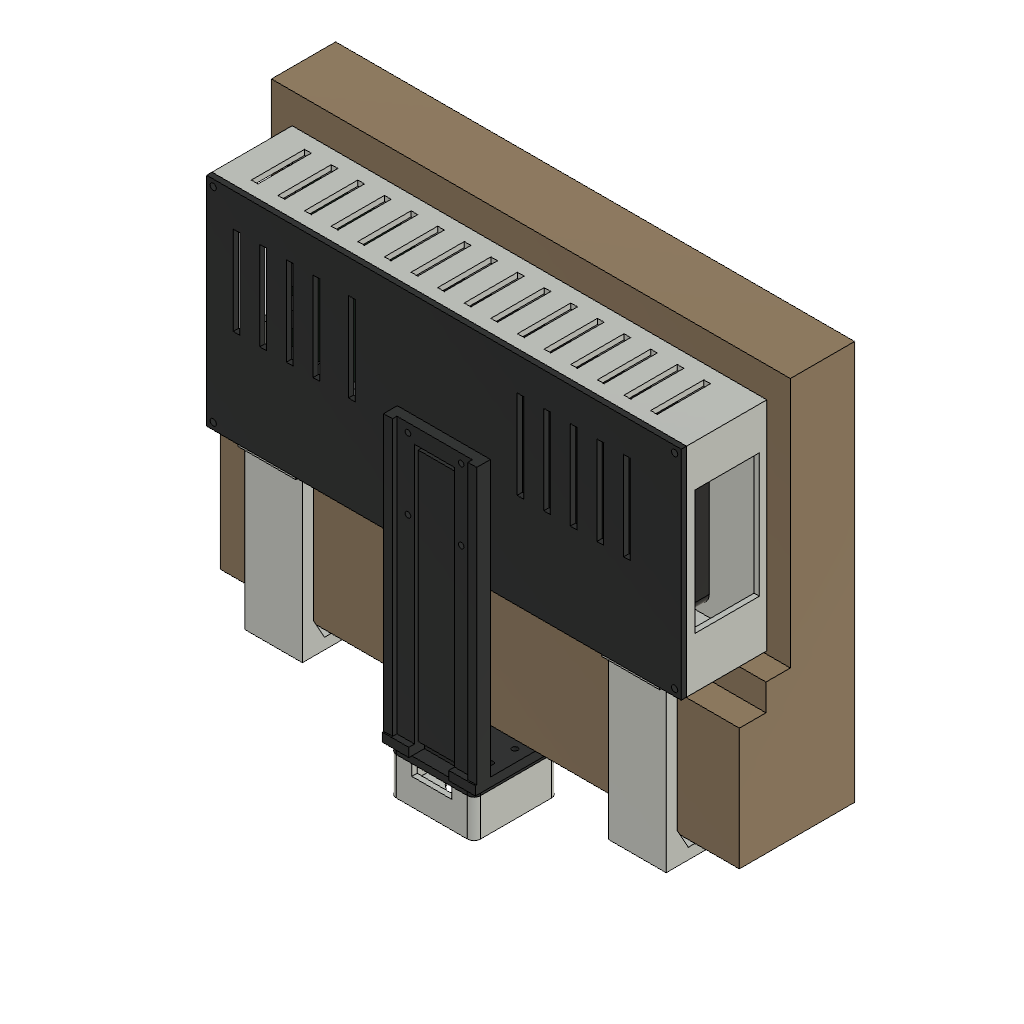
doorframe-camera-v5 (Autodesk Fusion 360 design; units mm, degrees)
part number: 2026-11-08-18-06-19-159
part number: 2026-11-08-18-06-29-546
part number: 2026-11-08-18-06-30-123
part number: 2026-11-08-18-06-36-129
part number: 2026-11-08-18-06-39-085
part number: 2026-11-08-18-06-42-850
part number: 2026-11-08-20-43-08-468
part number: 2026-11-08-20-43-10-155
part number: 2026-11-08-20-43-11-426
part number: 2026-11-08-20-43-11-993
part number: 2026-11-08-20-43-12-596
part number: 2026-11-08-20-43-14-141
part number: 2026-11-08-20-43-15-002
part number: 2026-11-08-20-43-15-243
Autodesk Fusion 360 part; units mm, degrees
(part 1 of 2)
ref_plane "WorkPlane1" through (0, 0, 4.4) normal (0, 0, 1) x (1, 0, 0) in component "REFERENCE - INIU P51L-E2 115 x 73 x 29 mm"
sketch "INIU envelope - check supplied cable position outline" plane through (0, 0, 4.4) normal (0, 0, 1) x (1, 0, 0) in component "REFERENCE - INIU P51L-E2 115 x 73 x 29 mm"
  line L0 (11, 7.5) -> (116, 7.5)
  line L1 (121, 12.5) -> (121, 75.5)
  line L2 (116, 80.5) -> (11, 80.5)
  line L3 (6, 75.5) -> (6, 12.5)
  arc A0 (116, 7.5) -> (121, 12.5) centre (116, 12.5) ccw
  arc A1 (121, 75.5) -> (116, 80.5) centre (116, 75.5) ccw
  arc A2 (11, 80.5) -> (6, 75.5) centre (11, 75.5) ccw
  arc A3 (6, 12.5) -> (11, 7.5) centre (11, 12.5) ccw
extrude "INIU envelope - check supplied cable position" add sketch "INIU envelope - check supplied cable position outline" along normal blind 29 makes body 1 in component "REFERENCE - INIU P51L-E2 115 x 73 x 29 mm"
ref_plane "WorkPlane1" through (0, 0, 44.4) normal (0, 0, 1) x (1, 0, 0) in component "REFERENCE - Raspberry Pi4 rotated ports"
sketch "Pi PCB 85 x 56 x 1.6 outline" plane through (0, 0, 44.4) normal (0, 0, 1) x (1, 0, 0) in component "REFERENCE - Raspberry Pi4 rotated ports"
  line L0 (9, 15) -> (88, 15)
  line L1 (91, 18) -> (91, 68)
  line L2 (88, 71) -> (9, 71)
  line L3 (6, 68) -> (6, 18)
  arc A0 (88, 15) -> (91, 18) centre (88, 18) ccw
  arc A1 (91, 68) -> (88, 71) centre (88, 68) ccw
  arc A2 (9, 71) -> (6, 68) centre (9, 68) ccw
  arc A3 (6, 18) -> (9, 15) centre (9, 18) ccw
extrude "Pi PCB 85 x 56 x 1.6" add sketch "Pi PCB 85 x 56 x 1.6 outline" along normal blind 1.6 separate body makes body 2 in component "REFERENCE - Raspberry Pi4 rotated ports"
ref_plane "WorkPlane2" through (0, 0, 44.3) normal (0, 0, 1) x (1, 0, 0) in component "REFERENCE - Raspberry Pi4 rotated ports"
sketch "Pi mounting holes layout" plane through (0, 0, 44.3) normal (0, 0, 1) x (1, 0, 0) in component "REFERENCE - Raspberry Pi4 rotated ports"
  circle A0 centre (87.5, 67.5) radius 1.375
  circle A1 centre (29.5, 67.5) radius 1.375
  circle A2 centre (87.5, 18.5) radius 1.375
  circle A3 centre (29.5, 18.5) radius 1.375
extrude "Pi mounting holes" cut sketch "Pi mounting holes layout" along normal blind 2 bodies 2 in component "REFERENCE - Raspberry Pi4 rotated ports"
ref_plane "WorkPlane3" through (0, 0, 46) normal (0, 0, 1) x (1, 0, 0) in component "REFERENCE - Raspberry Pi4 rotated ports"
sketch "USB3 outline" plane through (0, 0, 46) normal (0, 0, 1) x (1, 0, 0) in component "REFERENCE - Raspberry Pi4 rotated ports"
  line L0 (3, 55.4) -> (20.5, 55.4)
  line L1 (20.5, 55.4) -> (20.5, 68.6)
  line L2 (20.5, 68.6) -> (3, 68.6)
  line L3 (3, 68.6) -> (3, 55.4)
extrude "USB3" add sketch "USB3 outline" along normal blind 16 separate body makes body 3 in component "REFERENCE - Raspberry Pi4 rotated ports"
ref_plane "WorkPlane4" through (0, 0, 46) normal (0, 0, 1) x (1, 0, 0) in component "REFERENCE - Raspberry Pi4 rotated ports"
sketch "USB2 outline" plane through (0, 0, 46) normal (0, 0, 1) x (1, 0, 0) in component "REFERENCE - Raspberry Pi4 rotated ports"
  line L0 (3, 37.4) -> (20.5, 37.4)
  line L1 (20.5, 37.4) -> (20.5, 50.6)
  line L2 (20.5, 50.6) -> (3, 50.6)
  line L3 (3, 50.6) -> (3, 37.4)
extrude "USB2" add sketch "USB2 outline" along normal blind 16 separate body makes body 4 in component "REFERENCE - Raspberry Pi4 rotated ports"
ref_plane "WorkPlane5" through (0, 0, 46) normal (0, 0, 1) x (1, 0, 0) in component "REFERENCE - Raspberry Pi4 rotated ports"
sketch "Ethernet outline" plane through (0, 0, 46) normal (0, 0, 1) x (1, 0, 0) in component "REFERENCE - Raspberry Pi4 rotated ports"
  line L0 (3, 17.5) -> (24.5, 17.5)
  line L1 (24.5, 17.5) -> (24.5, 33.5)
  line L2 (24.5, 33.5) -> (3, 33.5)
  line L3 (3, 33.5) -> (3, 17.5)
extrude "Ethernet" add sketch "Ethernet outline" along normal blind 13.5 separate body makes body 5 in component "REFERENCE - Raspberry Pi4 rotated ports"
ref_plane "WorkPlane6" through (0, 0, 46) normal (0, 0, 1) x (1, 0, 0) in component "REFERENCE - Raspberry Pi4 rotated ports"
sketch "USB-C outline" plane through (0, 0, 46) normal (0, 0, 1) x (1, 0, 0) in component "REFERENCE - Raspberry Pi4 rotated ports"
  line L0 (73.5, 64) -> (86.1, 64)
  line L1 (86.1, 64) -> (86.1, 72)
  line L2 (86.1, 72) -> (73.5, 72)
  line L3 (73.5, 72) -> (73.5, 64)
extrude "USB-C" add sketch "USB-C outline" along normal blind 3.2 separate body makes body 6 in component "REFERENCE - Raspberry Pi4 rotated ports"
ref_plane "WorkPlane7" through (0, 0, 46) normal (0, 0, 1) x (1, 0, 0) in component "REFERENCE - Raspberry Pi4 rotated ports"
sketch "HDMI0 outline" plane through (0, 0, 46) normal (0, 0, 1) x (1, 0, 0) in component "REFERENCE - Raspberry Pi4 rotated ports"
  line L0 (60.5, 64) -> (69.5, 64)
  line L1 (69.5, 64) -> (69.5, 72)
  line L2 (69.5, 72) -> (60.5, 72)
  line L3 (60.5, 72) -> (60.5, 64)
extrude "HDMI0" add sketch "HDMI0 outline" along normal blind 3 separate body makes body 7 in component "REFERENCE - Raspberry Pi4 rotated ports"
ref_plane "WorkPlane8" through (0, 0, 46) normal (0, 0, 1) x (1, 0, 0) in component "REFERENCE - Raspberry Pi4 rotated ports"
sketch "HDMI1 outline" plane through (0, 0, 46) normal (0, 0, 1) x (1, 0, 0) in component "REFERENCE - Raspberry Pi4 rotated ports"
  line L0 (47, 64) -> (56, 64)
  line L1 (56, 64) -> (56, 72)
  line L2 (56, 72) -> (47, 72)
  line L3 (47, 72) -> (47, 64)
extrude "HDMI1" add sketch "HDMI1 outline" along normal blind 3 separate body makes body 8 in component "REFERENCE - Raspberry Pi4 rotated ports"
ref_plane "WorkPlane9" through (0, 0, 46) normal (0, 0, 1) x (1, 0, 0) in component "REFERENCE - Raspberry Pi4 rotated ports"
sketch "Audio outline" plane through (0, 0, 46) normal (0, 0, 1) x (1, 0, 0) in component "REFERENCE - Raspberry Pi4 rotated ports"
  line L0 (33.5, 58) -> (40.5, 58)
  line L1 (40.5, 58) -> (40.5, 72)
  line L2 (40.5, 72) -> (33.5, 72)
  line L3 (33.5, 72) -> (33.5, 58)
extrude "Audio" add sketch "Audio outline" along normal blind 6 separate body makes body 9 in component "REFERENCE - Raspberry Pi4 rotated ports"
sketch "Camera carrier outline" plane through (0, 0, 0) normal (0, 0, 1) x (1, 0, 0) in component "04 Camera G carrier - PRINT"
  line L0 (3, 0) -> (35, 0)
  line L1 (38, 3) -> (38, 35)
  line L2 (35, 38) -> (3, 38)
  line L3 (0, 35) -> (0, 3)
  arc A0 (35, 0) -> (38, 3) centre (35, 3) ccw
  arc A1 (38, 35) -> (35, 38) centre (35, 35) ccw
  arc A2 (3, 38) -> (0, 35) centre (3, 35) ccw
  arc A3 (0, 3) -> (3, 0) centre (3, 3) ccw
extrude "Camera carrier" add sketch "Camera carrier outline" along normal blind 3 separate body makes body 10 in component "04 Camera G carrier - PRINT"
ref_plane "WorkPlane1" through (0, 0, 3) normal (0, 0, 1) x (1, 0, 0) in component "04 Camera G carrier - PRINT"
sketch "Waveshare G PCB supports layout" plane through (0, 0, 3) normal (0, 0, 1) x (1, 0, 0) in component "04 Camera G carrier - PRINT"
  circle A0 centre (8.5, 14.5) radius 2.3
  circle A1 centre (29.5, 14.5) radius 2.3
  circle A2 centre (8.5, 28) radius 2.3
  circle A3 centre (29.5, 28) radius 2.3
extrude "Waveshare G PCB supports" add sketch "Waveshare G PCB supports layout" along normal blind 2.5 bodies 10 in component "04 Camera G carrier - PRINT"
sketch "M2 camera through holes - 21 x 13.5 mm layout" plane through (0, 0, 0) normal (0, 0, 1) x (1, 0, 0) in component "04 Camera G carrier - PRINT"
  circle A0 centre (8.5, 14.5) radius 1.15
  circle A1 centre (29.5, 14.5) radius 1.15
  circle A2 centre (8.5, 28) radius 1.15
  circle A3 centre (29.5, 28) radius 1.15
extrude "M2 camera through holes - 21 x 13.5 mm" cut sketch "M2 camera through holes - 21 x 13.5 mm layout" along normal blind 6 bodies 10 in component "04 Camera G carrier - PRINT"
sketch "M2 nut recesses layout" plane through (0, 0, 0) normal (0, 0, 1) x (1, 0, 0) in component "04 Camera G carrier - PRINT"
  circle A0 centre (8.5, 14.5) radius 2.35
  circle A1 centre (29.5, 14.5) radius 2.35
  circle A2 centre (8.5, 28) radius 2.35
  circle A3 centre (29.5, 28) radius 2.35
extrude "M2 nut recesses" cut sketch "M2 nut recesses layout" along normal blind 1.7 bodies 10 in component "04 Camera G carrier - PRINT"
sketch "Camera cap M2.5 clearance layout" plane through (0, 0, 0) normal (0, 0, 1) x (1, 0, 0) in component "04 Camera G carrier - PRINT"
  circle A0 centre (3.5, 3.5) radius 1.4
  circle A1 centre (34.5, 3.5) radius 1.4
  circle A2 centre (3.5, 34.5) radius 1.4
  circle A3 centre (34.5, 34.5) radius 1.4
extrude "Camera cap M2.5 clearance" cut sketch "Camera cap M2.5 clearance layout" along normal blind 3.2 bodies 10 in component "04 Camera G carrier - PRINT"
sketch "Camera bracket M3 clearance layout" plane through (0, 0, 0) normal (0, 0, 1) x (1, 0, 0) in component "04 Camera G carrier - PRINT"
  circle A0 centre (3.5, 11) radius 1.7
  circle A1 centre (34.5, 11) radius 1.7
  circle A2 centre (3.5, 22) radius 1.7
  circle A3 centre (34.5, 22) radius 1.7
extrude "Camera bracket M3 clearance" cut sketch "Camera bracket M3 clearance layout" along normal blind 3.2 bodies 10 in component "04 Camera G carrier - PRINT"
ref_plane "WorkPlane1" through (0, 0, 3) normal (0, 0, 1) x (1, 0, 0) in component "05 Camera G protective cap - PRINT"
sketch "Camera cap shell outline" plane through (0, 0, 3) normal (0, 0, 1) x (1, 0, 0) in component "05 Camera G protective cap - PRINT"
  line L0 (3, 0) -> (35, 0)
  line L1 (38, 3) -> (38, 35)
  line L2 (35, 38) -> (3, 38)
  line L3 (0, 35) -> (0, 3)
  arc A0 (35, 0) -> (38, 3) centre (35, 3) ccw
  arc A1 (38, 35) -> (35, 38) centre (35, 35) ccw
  arc A2 (3, 38) -> (0, 35) centre (3, 35) ccw
  arc A3 (0, 3) -> (3, 0) centre (3, 3) ccw
extrude "Camera cap shell" add sketch "Camera cap shell outline" along normal blind 17 separate body makes body 11 in component "05 Camera G protective cap - PRINT"
ref_plane "WorkPlane2" through (0, 0, 2.9) normal (0, 0, 1) x (1, 0, 0) in component "05 Camera G protective cap - PRINT"
sketch "Camera body clearance outline" plane through (0, 0, 2.9) normal (0, 0, 1) x (1, 0, 0) in component "05 Camera G protective cap - PRINT"
  line L0 (3, 2.4) -> (35, 2.4)
  line L1 (35.6, 3) -> (35.6, 35)
  line L2 (35, 35.6) -> (3, 35.6)
  line L3 (2.4, 35) -> (2.4, 3)
  arc A0 (35, 2.4) -> (35.6, 3) centre (35, 3) ccw
  arc A1 (35.6, 35) -> (35, 35.6) centre (35, 35) ccw
  arc A2 (3, 35.6) -> (2.4, 35) centre (3, 35) ccw
  arc A3 (2.4, 3) -> (3, 2.4) centre (3, 3) ccw
extrude "Camera body clearance" cut sketch "Camera body clearance outline" along normal blind 14.7 bodies 11 in component "05 Camera G protective cap - PRINT"
ref_plane "WorkPlane3" through (0, 0, 17.5) normal (0, 0, 1) x (1, 0, 0) in component "05 Camera G protective cap - PRINT"
sketch "Fisheye clearance" plane through (0, 0, 17.5) normal (0, 0, 1) x (1, 0, 0) in component "05 Camera G protective cap - PRINT"
  circle A0 centre (19, 21.65) radius 11
  dimension "d201" = 22
  measures "d201" diameter of A0
extrude "Fisheye aperture" cut sketch "Fisheye clearance" along normal blind 3 bodies 11 in component "05 Camera G protective cap - PRINT"
ref_plane "WorkPlane4" through (0, 0, 3) normal (0, 0, 1) x (1, 0, 0) in component "05 Camera G protective cap - PRINT"
sketch "Cap screw pillars layout" plane through (0, 0, 3) normal (0, 0, 1) x (1, 0, 0) in component "05 Camera G protective cap - PRINT"
  circle A0 centre (3.5, 3.5) radius 3
  circle A1 centre (34.5, 3.5) radius 3
  circle A2 centre (3.5, 34.5) radius 3
  circle A3 centre (34.5, 34.5) radius 3
extrude "Cap screw pillars" add sketch "Cap screw pillars layout" along normal blind 14.6 bodies 11 in component "05 Camera G protective cap - PRINT"
ref_plane "WorkPlane5" through (0, 0, 2.9) normal (0, 0, 1) x (1, 0, 0) in component "05 Camera G protective cap - PRINT"
sketch "M2.5 cap pilots layout" plane through (0, 0, 2.9) normal (0, 0, 1) x (1, 0, 0) in component "05 Camera G protective cap - PRINT"
  circle A0 centre (3.5, 3.5) radius 1.05
  circle A1 centre (34.5, 3.5) radius 1.05
  circle A2 centre (3.5, 34.5) radius 1.05
  circle A3 centre (34.5, 34.5) radius 1.05
extrude "M2.5 cap pilots" cut sketch "M2.5 cap pilots layout" along normal blind 8 bodies 11 in component "05 Camera G protective cap - PRINT"
ref_plane "WorkPlane6" through (0, 0, 3) normal (0, 0, 1) x (1, 0, 0) in component "05 Camera G protective cap - PRINT"
sketch "Ribbon cable exit layout" plane through (0, 0, 3) normal (0, 0, 1) x (1, 0, 0) in component "05 Camera G protective cap - PRINT"
  line L0 (10, -1) -> (28, -1)
  line L1 (28, -1) -> (28, 3)
  line L2 (28, 3) -> (10, 3)
  line L3 (10, 3) -> (10, -1)
extrude "Ribbon cable exit" cut sketch "Ribbon cable exit layout" along normal blind 5 bodies 11 in component "05 Camera G protective cap - PRINT"
ref_plane "WorkPlane1" through (0, 0, 5.5) normal (0, 0, 1) x (1, 0, 0) in component "REFERENCE - Waveshare RPi Camera G PCB and lens"
sketch "Camera PCB 25 x 24 outline" plane through (0, 0, 5.5) normal (0, 0, 1) x (1, 0, 0) in component "REFERENCE - Waveshare RPi Camera G PCB and lens"
  line L0 (6.5, 6) -> (31.5, 6)
  line L1 (31.5, 6) -> (31.5, 30)
  line L2 (31.5, 30) -> (6.5, 30)
  line L3 (6.5, 30) -> (6.5, 6)
extrude "Camera PCB 25 x 24" add sketch "Camera PCB 25 x 24 outline" along normal blind 1.2 separate body makes body 12 in component "REFERENCE - Waveshare RPi Camera G PCB and lens"
ref_plane "WorkPlane2" through (0, 0, 5.4) normal (0, 0, 1) x (1, 0, 0) in component "REFERENCE - Waveshare RPi Camera G PCB and lens"
sketch "Camera mounting holes layout" plane through (0, 0, 5.4) normal (0, 0, 1) x (1, 0, 0) in component "REFERENCE - Waveshare RPi Camera G PCB and lens"
  circle A0 centre (8.5, 14.5) radius 1.1
  circle A1 centre (29.5, 14.5) radius 1.1
  circle A2 centre (8.5, 28) radius 1.1
  circle A3 centre (29.5, 28) radius 1.1
extrude "Camera mounting holes" cut sketch "Camera mounting holes layout" along normal blind 1.5 bodies 12 in component "REFERENCE - Waveshare RPi Camera G PCB and lens"
ref_plane "WorkPlane3" through (0, 0, 6.7) normal (0, 0, 1) x (1, 0, 0) in component "REFERENCE - Waveshare RPi Camera G PCB and lens"
sketch "Approximate fisheye barrel - verify height layout" plane through (0, 0, 6.7) normal (0, 0, 1) x (1, 0, 0) in component "REFERENCE - Waveshare RPi Camera G PCB and lens"
  circle A0 centre (19, 21.65) radius 8
extrude "Approximate fisheye barrel - verify height" add sketch "Approximate fisheye barrel - verify height layout" along normal blind 18 separate body makes body 13 in component "REFERENCE - Waveshare RPi Camera G PCB and lens"
ref_plane "WorkPlane1" through (0, 0, 69) normal (0, 0, 1) x (1, 0, 0) in component "01 Upright Pi and battery shell - PRINT"
sketch "Upright open-front shell outline" plane through (0, 0, 69) normal (0, 0, 1) x (1, 0, 0) in component "01 Upright Pi and battery shell - PRINT"
  line L0 (0, -13.8) -> (214, -13.8)
  line L1 (214, -13.8) -> (214, 22.4)
  line L2 (214, 22.4) -> (0, 22.4)
  line L3 (0, 22.4) -> (0, -13.8)
extrude "Upright open-front shell" add sketch "Upright open-front shell outline" along normal blind 98 separate body makes body 14 in component "01 Upright Pi and battery shell - PRINT"
ref_plane "WorkPlane2" through (0, 0, 71.4) normal (0, 0, 1) x (1, 0, 0) in component "01 Upright Pi and battery shell - PRINT"
sketch "Electronics cavity outline" plane through (0, 0, 71.4) normal (0, 0, 1) x (1, 0, 0) in component "01 Upright Pi and battery shell - PRINT"
  line L0 (2.4, -14) -> (211.6, -14)
  line L1 (211.6, -14) -> (211.6, 20)
  line L2 (211.6, 20) -> (2.4, 20)
  line L3 (2.4, 20) -> (2.4, -14)
extrude "Electronics cavity" cut sketch "Electronics cavity outline" along normal blind 93.2 bodies 14 in component "01 Upright Pi and battery shell - PRINT"
ref_plane "WorkPlane3" through (0, -13.8, 0) normal (0, 1, 0) x (0, 0, 1) in component "01 Upright Pi and battery shell - PRINT"
sketch "Front panel screw pillars layout" plane through (0, -13.8, 0) normal (0, 1, 0) x (1, 0, 0) in component "01 Upright Pi and battery shell - PRINT"
  circle A0 centre (3, -72) radius 3
  circle A1 centre (211, -72) radius 3
  circle A2 centre (3, -164) radius 3
  circle A3 centre (211, -164) radius 3
extrude "Front panel screw pillars" add sketch "Front panel screw pillars layout" along normal blind 33.8 bodies 14 in component "01 Upright Pi and battery shell - PRINT"
ref_plane "WorkPlane4" through (0, -13.9, 0) normal (0, 1, 0) x (0, 0, 1) in component "01 Upright Pi and battery shell - PRINT"
sketch "M2.5 front panel pilots layout" plane through (0, -13.9, 0) normal (0, 1, 0) x (1, 0, 0) in component "01 Upright Pi and battery shell - PRINT"
  circle A0 centre (3, -72) radius 1.05
  circle A1 centre (211, -72) radius 1.05
  circle A2 centre (3, -164) radius 1.05
  circle A3 centre (211, -164) radius 1.05
extrude "M2.5 front panel pilots" cut sketch "M2.5 front panel pilots layout" along normal blind 6 bodies 14 in component "01 Upright Pi and battery shell - PRINT"
ref_plane "WorkPlane5" through (0, 20, 0) normal (0, 1, 0) x (0, 0, 1) in component "01 Upright Pi and battery shell - PRINT"
sketch "Vertical Pi standoffs layout" plane through (0, 20, 0) normal (0, 1, 0) x (1, 0, 0) in component "01 Upright Pi and battery shell - PRINT"
  circle A0 centre (9.5, -98.5) radius 3
  circle A1 centre (58.5, -98.5) radius 3
  circle A2 centre (9.5, -156.5) radius 3
  circle A3 centre (58.5, -156.5) radius 3
extrude "Vertical Pi standoffs" add sketch "Vertical Pi standoffs layout" against normal blind 4.4 bodies 14 in component "01 Upright Pi and battery shell - PRINT"
ref_plane "WorkPlane6" through (0, 15.5, 0) normal (0, 1, 0) x (0, 0, 1) in component "01 Upright Pi and battery shell - PRINT"
sketch "Pi M2.5 pilots layout" plane through (0, 15.5, 0) normal (0, 1, 0) x (1, 0, 0) in component "01 Upright Pi and battery shell - PRINT"
  circle A0 centre (9.5, -98.5) radius 1.05
  circle A1 centre (58.5, -98.5) radius 1.05
  circle A2 centre (9.5, -156.5) radius 1.05
  circle A3 centre (58.5, -156.5) radius 1.05
extrude "Pi M2.5 pilots" cut sketch "Pi M2.5 pilots layout" along normal blind 4.6 bodies 14 in component "01 Upright Pi and battery shell - PRINT"
ref_plane "WorkPlane7" through (0, 0, 99) normal (0, 0, 1) x (1, 0, 0) in component "01 Upright Pi and battery shell - PRINT"
sketch "Pi power and HDMI side access outline" plane through (0, 0, 99) normal (0, 0, 1) x (1, 0, 0) in component "01 Upright Pi and battery shell - PRINT"
  line L0 (-1, -5) -> (3.2, -5)
  line L1 (3.2, -5) -> (3.2, 18)
  line L2 (3.2, 18) -> (-1, 18)
  line L3 (-1, 18) -> (-1, -5)
extrude "Pi power and HDMI side access" cut sketch "Pi power and HDMI side access outline" along normal blind 58 bodies 14 in component "01 Upright Pi and battery shell - PRINT"
ref_plane "WorkPlane8" through (0, 0, 92) normal (0, 0, 1) x (1, 0, 0) in component "01 Upright Pi and battery shell - PRINT"
sketch "Battery cable and button access outline" plane through (0, 0, 92) normal (0, 0, 1) x (1, 0, 0) in component "01 Upright Pi and battery shell - PRINT"
  line L0 (210.8, -10) -> (215, -10)
  line L1 (215, -10) -> (215, 19)
  line L2 (215, 19) -> (210.8, 19)
  line L3 (210.8, 19) -> (210.8, -10)
extrude "Battery cable and button access" cut sketch "Battery cable and button access outline" along normal blind 56 bodies 14 in component "01 Upright Pi and battery shell - PRINT"
ref_plane "WorkPlane9" through (0, 0, 164.5) normal (0, 0, 1) x (1, 0, 0) in component "01 Upright Pi and battery shell - PRINT"
sketch "Top air slots layout" plane through (0, 0, 164.5) normal (0, 0, 1) x (1, 0, 0) in component "01 Upright Pi and battery shell - PRINT"
  line L0 (12, -8) -> (15, -8)
  line L1 (15, -8) -> (15, 16)
  line L2 (15, 16) -> (12, 16)
  line L3 (12, 16) -> (12, -8)
  line L4 (24, -8) -> (27, -8)
  line L5 (27, -8) -> (27, 16)
  line L6 (27, 16) -> (24, 16)
  line L7 (24, 16) -> (24, -8)
  line L8 (36, -8) -> (39, -8)
  line L9 (39, -8) -> (39, 16)
  line L10 (39, 16) -> (36, 16)
  line L11 (36, 16) -> (36, -8)
  line L12 (48, -8) -> (51, -8)
  line L13 (51, -8) -> (51, 16)
  line L14 (51, 16) -> (48, 16)
  line L15 (48, 16) -> (48, -8)
  line L16 (60, -8) -> (63, -8)
  line L17 (63, -8) -> (63, 16)
  line L18 (63, 16) -> (60, 16)
  line L19 (60, 16) -> (60, -8)
  line L20 (72, -8) -> (75, -8)
  line L21 (75, -8) -> (75, 16)
  line L22 (75, 16) -> (72, 16)
  line L23 (72, 16) -> (72, -8)
  line L24 (84, -8) -> (87, -8)
  line L25 (87, -8) -> (87, 16)
  line L26 (87, 16) -> (84, 16)
  line L27 (84, 16) -> (84, -8)
  line L28 (96, -8) -> (99, -8)
  line L29 (99, -8) -> (99, 16)
  line L30 (99, 16) -> (96, 16)
  line L31 (96, 16) -> (96, -8)
  line L32 (108, -8) -> (111, -8)
  line L33 (111, -8) -> (111, 16)
  line L34 (111, 16) -> (108, 16)
  line L35 (108, 16) -> (108, -8)
  line L36 (120, -8) -> (123, -8)
  line L37 (123, -8) -> (123, 16)
  line L38 (123, 16) -> (120, 16)
  line L39 (120, 16) -> (120, -8)
  line L40 (132, -8) -> (135, -8)
  line L41 (135, -8) -> (135, 16)
  line L42 (135, 16) -> (132, 16)
  line L43 (132, 16) -> (132, -8)
  line L44 (144, -8) -> (147, -8)
  line L45 (147, -8) -> (147, 16)
  line L46 (147, 16) -> (144, 16)
  line L47 (144, 16) -> (144, -8)
  line L48 (156, -8) -> (159, -8)
  line L49 (159, -8) -> (159, 16)
  line L50 (159, 16) -> (156, 16)
  line L51 (156, 16) -> (156, -8)
  line L52 (168, -8) -> (171, -8)
  line L53 (171, -8) -> (171, 16)
  line L54 (171, 16) -> (168, 16)
  line L55 (168, 16) -> (168, -8)
  line L56 (180, -8) -> (183, -8)
  line L57 (183, -8) -> (183, 16)
  line L58 (183, 16) -> (180, 16)
  line L59 (180, 16) -> (180, -8)
  line L60 (192, -8) -> (195, -8)
  line L61 (195, -8) -> (195, 16)
  line L62 (195, 16) -> (192, 16)
  line L63 (192, 16) -> (192, -8)
extrude "Top air slots" cut sketch "Top air slots layout" along normal blind 2.6 bodies 14 in component "01 Upright Pi and battery shell - PRINT"
ref_plane "WorkPlane10" through (0, 0, 68.9) normal (0, 0, 1) x (1, 0, 0) in component "01 Upright Pi and battery shell - PRINT"
sketch "Battery strap slots layout" plane through (0, 0, 68.9) normal (0, 0, 1) x (1, 0, 0) in component "01 Upright Pi and battery shell - PRINT"
  line L0 (116, -10.8) -> (128, -10.8)
  line L1 (128, -10.8) -> (128, -8.6)
  line L2 (128, -8.6) -> (116, -8.6)
  line L3 (116, -8.6) -> (116, -10.8)
  line L4 (116, 18.6) -> (128, 18.6)
  line L5 (128, 18.6) -> (128, 20.8)
  line L6 (128, 20.8) -> (116, 20.8)
  line L7 (116, 20.8) -> (116, 18.6)
  line L8 (160, -10.8) -> (172, -10.8)
  line L9 (172, -10.8) -> (172, -8.6)
  line L10 (172, -8.6) -> (160, -8.6)
  line L11 (160, -8.6) -> (160, -10.8)
  line L12 (160, 18.6) -> (172, 18.6)
  line L13 (172, 18.6) -> (172, 20.8)
  line L14 (172, 20.8) -> (160, 20.8)
  line L15 (160, 20.8) -> (160, 18.6)
extrude "Battery strap slots" cut sketch "Battery strap slots layout" along normal blind 2.6 bodies 14 in component "01 Upright Pi and battery shell - PRINT"
ref_plane "WorkPlane11" through (0, 0, 57) normal (0, 0, 1) x (1, 0, 0) in component "01 Upright Pi and battery shell - PRINT"
sketch "Lower-ledge foot 1 outline" plane through (0, 0, 57) normal (0, 0, 1) x (1, 0, 0) in component "01 Upright Pi and battery shell - PRINT"
  line L0 (15, 0.5) -> (35, 0.5)
  line L1 (35, 0.5) -> (35, 10.5)
  line L2 (35, 10.5) -> (15, 10.5)
  line L3 (15, 10.5) -> (15, 0.5)
extrude "Lower-ledge foot 1" add sketch "Lower-ledge foot 1 outline" along normal blind 12 bodies 14 in component "01 Upright Pi and battery shell - PRINT"
ref_plane "WorkPlane12" through (0, 0, 56.9) normal (0, 0, 1) x (1, 0, 0) in component "01 Upright Pi and battery shell - PRINT"
sketch "Lower-ledge pad recess 1 layout" plane through (0, 0, 56.9) normal (0, 0, 1) x (1, 0, 0) in component "01 Upright Pi and battery shell - PRINT"
  line L0 (15, 0.5) -> (35, 0.5)
  line L1 (35, 0.5) -> (35, 10.5)
  line L2 (35, 10.5) -> (15, 10.5)
  line L3 (15, 10.5) -> (15, 0.5)
extrude "Lower-ledge pad recess 1" cut sketch "Lower-ledge pad recess 1 layout" along normal blind 0.6 bodies 14 in component "01 Upright Pi and battery shell - PRINT"
ref_plane "WorkPlane13" through (0, 0, 57) normal (0, 0, 1) x (1, 0, 0) in component "01 Upright Pi and battery shell - PRINT"
sketch "Lower-ledge foot 2 outline" plane through (0, 0, 57) normal (0, 0, 1) x (1, 0, 0) in component "01 Upright Pi and battery shell - PRINT"
  line L0 (179, 0.5) -> (199, 0.5)
  line L1 (199, 0.5) -> (199, 10.5)
  line L2 (199, 10.5) -> (179, 10.5)
  line L3 (179, 10.5) -> (179, 0.5)
extrude "Lower-ledge foot 2" add sketch "Lower-ledge foot 2 outline" along normal blind 12 bodies 14 in component "01 Upright Pi and battery shell - PRINT"
ref_plane "WorkPlane14" through (0, 0, 56.9) normal (0, 0, 1) x (1, 0, 0) in component "01 Upright Pi and battery shell - PRINT"
sketch "Lower-ledge pad recess 2 layout" plane through (0, 0, 56.9) normal (0, 0, 1) x (1, 0, 0) in component "01 Upright Pi and battery shell - PRINT"
  line L0 (179, 0.5) -> (199, 0.5)
  line L1 (199, 0.5) -> (199, 10.5)
  line L2 (199, 10.5) -> (179, 10.5)
  line L3 (179, 10.5) -> (179, 0.5)
extrude "Lower-ledge pad recess 2" cut sketch "Lower-ledge pad recess 2 layout" along normal blind 0.6 bodies 14 in component "01 Upright Pi and battery shell - PRINT"
ref_plane "WorkPlane15" through (0, 0, 68.9) normal (0, 0, 1) x (1, 0, 0) in component "01 Upright Pi and battery shell - PRINT"
sketch "Upper-ledge pad recesses layout" plane through (0, 0, 68.9) normal (0, 0, 1) x (1, 0, 0) in component "01 Upright Pi and battery shell - PRINT"
  line L0 (15, 13) -> (35, 13)
  line L1 (35, 13) -> (35, 22)
  line L2 (35, 22) -> (15, 22)
  line L3 (15, 22) -> (15, 13)
  line L4 (179, 13) -> (199, 13)
  line L5 (199, 13) -> (199, 22)
  line L6 (199, 22) -> (179, 22)
  line L7 (179, 22) -> (179, 13)
extrude "Upper-ledge pad recesses" cut sketch "Upper-ledge pad recesses layout" along normal blind 0.6 bodies 14 in component "01 Upright Pi and battery shell - PRINT"
ref_plane "WorkPlane16" through (0, 0, 68.9) normal (0, 0, 1) x (1, 0, 0) in component "01 Upright Pi and battery shell - PRINT"
sketch "Bench saddle attachment M3 clearance layout" plane through (0, 0, 68.9) normal (0, 0, 1) x (1, 0, 0) in component "01 Upright Pi and battery shell - PRINT"
  circle A0 centre (20, -8.5) radius 1.7
  circle A1 centre (30, -8.5) radius 1.7
  circle A2 centre (184, -8.5) radius 1.7
  circle A3 centre (194, -8.5) radius 1.7
extrude "Bench saddle attachment M3 clearance" cut sketch "Bench saddle attachment M3 clearance layout" along normal blind 2.6 bodies 14 in component "01 Upright Pi and battery shell - PRINT"
ref_plane "WorkPlane1" through (0, 0, 69) normal (0, 0, 1) x (1, 0, 0) in component "02 Vented front service panel - PRINT"
sketch "Removable front panel outline" plane through (0, 0, 69) normal (0, 0, 1) x (1, 0, 0) in component "02 Vented front service panel - PRINT"
  line L0 (0, -16.2) -> (214, -16.2)
  line L1 (214, -16.2) -> (214, -13.8)
  line L2 (214, -13.8) -> (0, -13.8)
  line L3 (0, -13.8) -> (0, -16.2)
extrude "Removable front panel" add sketch "Removable front panel outline" along normal blind 98 separate body makes body 15 in component "02 Vented front service panel - PRINT"
ref_plane "WorkPlane2" through (0, -16.3, 0) normal (0, 1, 0) x (0, 0, 1) in component "02 Vented front service panel - PRINT"
sketch "M2.5 panel clearance layout" plane through (0, -16.3, 0) normal (0, 1, 0) x (1, 0, 0) in component "02 Vented front service panel - PRINT"
  circle A0 centre (3, -72) radius 1.4
  circle A1 centre (211, -72) radius 1.4
  circle A2 centre (3, -164) radius 1.4
  circle A3 centre (211, -164) radius 1.4
extrude "M2.5 panel clearance" cut sketch "M2.5 panel clearance layout" along normal blind 2.6 bodies 15 in component "02 Vented front service panel - PRINT"
ref_plane "WorkPlane3" through (0, 0, 112) normal (0, 0, 1) x (1, 0, 0) in component "02 Vented front service panel - PRINT"
sketch "Vertical air slot 12 outline" plane through (0, 0, 112) normal (0, 0, 1) x (1, 0, 0) in component "02 Vented front service panel - PRINT"
  line L0 (12, -16.3) -> (15, -16.3)
  line L1 (15, -16.3) -> (15, -13.7)
  line L2 (15, -13.7) -> (12, -13.7)
  line L3 (12, -13.7) -> (12, -16.3)
extrude "Vertical air slot 12" cut sketch "Vertical air slot 12 outline" along normal blind 40 bodies 15 in component "02 Vented front service panel - PRINT"
ref_plane "WorkPlane4" through (0, 0, 112) normal (0, 0, 1) x (1, 0, 0) in component "02 Vented front service panel - PRINT"
sketch "Vertical air slot 24 outline" plane through (0, 0, 112) normal (0, 0, 1) x (1, 0, 0) in component "02 Vented front service panel - PRINT"
  line L0 (24, -16.3) -> (27, -16.3)
  line L1 (27, -16.3) -> (27, -13.7)
  line L2 (27, -13.7) -> (24, -13.7)
  line L3 (24, -13.7) -> (24, -16.3)
extrude "Vertical air slot 24" cut sketch "Vertical air slot 24 outline" along normal blind 40 bodies 15 in component "02 Vented front service panel - PRINT"
ref_plane "WorkPlane5" through (0, 0, 112) normal (0, 0, 1) x (1, 0, 0) in component "02 Vented front service panel - PRINT"
sketch "Vertical air slot 36 outline" plane through (0, 0, 112) normal (0, 0, 1) x (1, 0, 0) in component "02 Vented front service panel - PRINT"
  line L0 (36, -16.3) -> (39, -16.3)
  line L1 (39, -16.3) -> (39, -13.7)
  line L2 (39, -13.7) -> (36, -13.7)
  line L3 (36, -13.7) -> (36, -16.3)
extrude "Vertical air slot 36" cut sketch "Vertical air slot 36 outline" along normal blind 40 bodies 15 in component "02 Vented front service panel - PRINT"
ref_plane "WorkPlane6" through (0, 0, 112) normal (0, 0, 1) x (1, 0, 0) in component "02 Vented front service panel - PRINT"
sketch "Vertical air slot 48 outline" plane through (0, 0, 112) normal (0, 0, 1) x (1, 0, 0) in component "02 Vented front service panel - PRINT"
  line L0 (48, -16.3) -> (51, -16.3)
  line L1 (51, -16.3) -> (51, -13.7)
  line L2 (51, -13.7) -> (48, -13.7)
  line L3 (48, -13.7) -> (48, -16.3)
extrude "Vertical air slot 48" cut sketch "Vertical air slot 48 outline" along normal blind 40 bodies 15 in component "02 Vented front service panel - PRINT"
ref_plane "WorkPlane7" through (0, 0, 112) normal (0, 0, 1) x (1, 0, 0) in component "02 Vented front service panel - PRINT"
sketch "Vertical air slot 64 outline" plane through (0, 0, 112) normal (0, 0, 1) x (1, 0, 0) in component "02 Vented front service panel - PRINT"
  line L0 (64, -16.3) -> (67, -16.3)
  line L1 (67, -16.3) -> (67, -13.7)
  line L2 (67, -13.7) -> (64, -13.7)
  line L3 (64, -13.7) -> (64, -16.3)
extrude "Vertical air slot 64" cut sketch "Vertical air slot 64 outline" along normal blind 40 bodies 15 in component "02 Vented front service panel - PRINT"
ref_plane "WorkPlane8" through (0, 0, 112) normal (0, 0, 1) x (1, 0, 0) in component "02 Vented front service panel - PRINT"
sketch "Vertical air slot 140 outline" plane through (0, 0, 112) normal (0, 0, 1) x (1, 0, 0) in component "02 Vented front service panel - PRINT"
  line L0 (140, -16.3) -> (143, -16.3)
  line L1 (143, -16.3) -> (143, -13.7)
  line L2 (143, -13.7) -> (140, -13.7)
  line L3 (140, -13.7) -> (140, -16.3)
extrude "Vertical air slot 140" cut sketch "Vertical air slot 140 outline" along normal blind 40 bodies 15 in component "02 Vented front service panel - PRINT"
ref_plane "WorkPlane9" through (0, 0, 112) normal (0, 0, 1) x (1, 0, 0) in component "02 Vented front service panel - PRINT"
sketch "Vertical air slot 152 outline" plane through (0, 0, 112) normal (0, 0, 1) x (1, 0, 0) in component "02 Vented front service panel - PRINT"
  line L0 (152, -16.3) -> (155, -16.3)
  line L1 (155, -16.3) -> (155, -13.7)
  line L2 (155, -13.7) -> (152, -13.7)
  line L3 (152, -13.7) -> (152, -16.3)
extrude "Vertical air slot 152" cut sketch "Vertical air slot 152 outline" along normal blind 40 bodies 15 in component "02 Vented front service panel - PRINT"
ref_plane "WorkPlane10" through (0, 0, 112) normal (0, 0, 1) x (1, 0, 0) in component "02 Vented front service panel - PRINT"
sketch "Vertical air slot 164 outline" plane through (0, 0, 112) normal (0, 0, 1) x (1, 0, 0) in component "02 Vented front service panel - PRINT"
  line L0 (164, -16.3) -> (167, -16.3)
  line L1 (167, -16.3) -> (167, -13.7)
  line L2 (167, -13.7) -> (164, -13.7)
  line L3 (164, -13.7) -> (164, -16.3)
extrude "Vertical air slot 164" cut sketch "Vertical air slot 164 outline" along normal blind 40 bodies 15 in component "02 Vented front service panel - PRINT"
ref_plane "WorkPlane11" through (0, 0, 112) normal (0, 0, 1) x (1, 0, 0) in component "02 Vented front service panel - PRINT"
sketch "Vertical air slot 176 outline" plane through (0, 0, 112) normal (0, 0, 1) x (1, 0, 0) in component "02 Vented front service panel - PRINT"
  line L0 (176, -16.3) -> (179, -16.3)
  line L1 (179, -16.3) -> (179, -13.7)
  line L2 (179, -13.7) -> (176, -13.7)
  line L3 (176, -13.7) -> (176, -16.3)
extrude "Vertical air slot 176" cut sketch "Vertical air slot 176 outline" along normal blind 40 bodies 15 in component "02 Vented front service panel - PRINT"
ref_plane "WorkPlane12" through (0, 0, 112) normal (0, 0, 1) x (1, 0, 0) in component "02 Vented front service panel - PRINT"
sketch "Vertical air slot 188 outline" plane through (0, 0, 112) normal (0, 0, 1) x (1, 0, 0) in component "02 Vented front service panel - PRINT"
  line L0 (188, -16.3) -> (191, -16.3)
  line L1 (191, -16.3) -> (191, -13.7)
  line L2 (191, -13.7) -> (188, -13.7)
  line L3 (188, -13.7) -> (188, -16.3)
extrude "Vertical air slot 188" cut sketch "Vertical air slot 188 outline" along normal blind 40 bodies 15 in component "02 Vented front service panel - PRINT"
ref_plane "WorkPlane13" through (0, 0, 110) normal (0, 0, 1) x (1, 0, 0) in component "02 Vented front service panel - PRINT"
sketch "Camera ribbon entry outline" plane through (0, 0, 110) normal (0, 0, 1) x (1, 0, 0) in component "02 Vented front service panel - PRINT"
  line L0 (98, -16.3) -> (116, -16.3)
  line L1 (116, -16.3) -> (116, -13.7)
  line L2 (116, -13.7) -> (98, -13.7)
  line L3 (98, -13.7) -> (98, -16.3)
extrude "Camera ribbon entry" cut sketch "Camera ribbon entry outline" along normal blind 3 bodies 15 in component "02 Vented front service panel - PRINT"
ref_plane "WorkPlane14" through (0, -16.3, 0) normal (0, 1, 0) x (0, 0, 1) in component "02 Vented front service panel - PRINT"
sketch "Camera support M3 clearance layout" plane through (0, -16.3, 0) normal (0, 1, 0) x (1, 0, 0) in component "02 Vented front service panel - PRINT"
  circle A0 centre (95, -84) radius 1.7
  circle A1 centre (119, -84) radius 1.7
  circle A2 centre (95, -116) radius 1.7
  circle A3 centre (119, -116) radius 1.7
extrude "Camera support M3 clearance" cut sketch "Camera support M3 clearance layout" along normal blind 2.6 bodies 15 in component "02 Vented front service panel - PRINT"
ref_plane "WorkPlane1" through (15, 0, 0) normal (1, 0, 0) x (0, 1, 0) in component "03 left passive retaining saddle - PRINT"
sketch "Fixed retaining saddle outline" plane through (15, 0, 0) normal (1, 0, 0) x (0, 0, -1) in component "03 left passive retaining saddle - PRINT"
  line L0 (7, -11) -> (7, 45)
  line L1 (7, 45) -> (2, 45)
  line L2 (2, 45) -> (2, -1)
  line L3 (2, -1) -> (-7, -6)
  line L4 (-7, -6) -> (-66, -6)
  line L5 (-66, -6) -> (-66, -11)
  line L6 (-66, -11) -> (7, -11)
extrude "Fixed retaining saddle" add sketch "Fixed retaining saddle outline" along normal blind 20 separate body makes body 16 in component "03 left passive retaining saddle - PRINT"
ref_plane "WorkPlane2" through (0, 0, 66) normal (0, 0, 1) x (1, 0, 0) in component "03 left passive retaining saddle - PRINT"
sketch "Bench attachment flange outline" plane through (0, 0, 66) normal (0, 0, 1) x (1, 0, 0) in component "03 left passive retaining saddle - PRINT"
  line L0 (12, -14) -> (38, -14)
  line L1 (38, -14) -> (38, -3)
  line L2 (38, -3) -> (12, -3)
  line L3 (12, -3) -> (12, -14)
extrude "Bench attachment flange" add sketch "Bench attachment flange outline" along normal blind 3 bodies 16 in component "03 left passive retaining saddle - PRINT"
ref_plane "WorkPlane3" through (0, 0, 69.1) normal (0, 0, 1) x (1, 0, 0) in component "03 left passive retaining saddle - PRINT"
sketch "M3 saddle pilots layout" plane through (0, 0, 69.1) normal (0, 0, 1) x (1, 0, 0) in component "03 left passive retaining saddle - PRINT"
  circle A0 centre (20, -8.5) radius 1.25
  circle A1 centre (30, -8.5) radius 1.25
extrude "M3 saddle pilots" cut sketch "M3 saddle pilots layout" against normal blind 7.1 bodies 16 in component "03 left passive retaining saddle - PRINT"
ref_plane "WorkPlane4" through (0, 0, -2.5) normal (0, 0, 1) x (1, 0, 0) in component "03 left passive retaining saddle - PRINT"
sketch "Underside rubber pocket layout" plane through (0, 0, -2.5) normal (0, 0, 1) x (1, 0, 0) in component "03 left passive retaining saddle - PRINT"
  line L0 (17, 30) -> (33, 30)
  line L1 (33, 30) -> (33, 44)
  line L2 (33, 44) -> (17, 44)
  line L3 (17, 44) -> (17, 30)
extrude "Underside rubber pocket" cut sketch "Underside rubber pocket layout" along normal blind 0.6 bodies 16 in component "03 left passive retaining saddle - PRINT"
ref_plane "WorkPlane5" through (14.9, 0, 0) normal (1, 0, 0) x (0, 1, 0) in component "03 left passive retaining saddle - PRINT"
sketch "Entry lead-in outline" plane through (14.9, 0, 0) normal (1, 0, 0) x (0, 0, -1) in component "03 left passive retaining saddle - PRINT"
  line L0 (2, 44.5) -> (2, 45)
  line L1 (2, 45) -> (2.5, 45)
  line L2 (2.5, 45) -> (2, 44.5)
extrude "Entry lead-in" cut sketch "Entry lead-in outline" along normal blind 20.2 bodies 16 in component "03 left passive retaining saddle - PRINT"
ref_plane "WorkPlane1" through (179, 0, 0) normal (1, 0, 0) x (0, 1, 0) in component "03 right passive retaining saddle - PRINT"
sketch "Fixed retaining saddle outline (2)" plane through (179, 0, 0) normal (1, 0, 0) x (0, 0, -1) in component "03 right passive retaining saddle - PRINT"
  line L0 (7, -11) -> (7, 45)
  line L1 (7, 45) -> (2, 45)
  line L2 (2, 45) -> (2, -1)
  line L3 (2, -1) -> (-7, -6)
  line L4 (-7, -6) -> (-66, -6)
  line L5 (-66, -6) -> (-66, -11)
  line L6 (-66, -11) -> (7, -11)
extrude "Fixed retaining saddle'" add sketch "Fixed retaining saddle outline (2)" along normal blind 20 separate body makes body 17 in component "03 right passive retaining saddle - PRINT"
ref_plane "WorkPlane2" through (0, 0, 66) normal (0, 0, 1) x (1, 0, 0) in component "03 right passive retaining saddle - PRINT"
sketch "Bench attachment flange outline (2)" plane through (0, 0, 66) normal (0, 0, 1) x (1, 0, 0) in component "03 right passive retaining saddle - PRINT"
  line L0 (176, -14) -> (202, -14)
  line L1 (202, -14) -> (202, -3)
  line L2 (202, -3) -> (176, -3)
  line L3 (176, -3) -> (176, -14)
extrude "Bench attachment flange'" add sketch "Bench attachment flange outline (2)" along normal blind 3 bodies 17 in component "03 right passive retaining saddle - PRINT"
ref_plane "WorkPlane3" through (0, 0, 69.1) normal (0, 0, 1) x (1, 0, 0) in component "03 right passive retaining saddle - PRINT"
sketch "M3 saddle pilots layout (2)" plane through (0, 0, 69.1) normal (0, 0, 1) x (1, 0, 0) in component "03 right passive retaining saddle - PRINT"
  circle A0 centre (184, -8.5) radius 1.25
  circle A1 centre (194, -8.5) radius 1.25
extrude "M3 saddle pilots'" cut sketch "M3 saddle pilots layout (2)" against normal blind 7.1 bodies 17 in component "03 right passive retaining saddle - PRINT"
ref_plane "WorkPlane4" through (0, 0, -2.5) normal (0, 0, 1) x (1, 0, 0) in component "03 right passive retaining saddle - PRINT"
sketch "Underside rubber pocket layout (2)" plane through (0, 0, -2.5) normal (0, 0, 1) x (1, 0, 0) in component "03 right passive retaining saddle - PRINT"
  line L0 (181, 30) -> (197, 30)
  line L1 (197, 30) -> (197, 44)
  line L2 (197, 44) -> (181, 44)
  line L3 (181, 44) -> (181, 30)
extrude "Underside rubber pocket'" cut sketch "Underside rubber pocket layout (2)" along normal blind 0.6 bodies 17 in component "03 right passive retaining saddle - PRINT"
ref_plane "WorkPlane5" through (178.9, 0, 0) normal (1, 0, 0) x (0, 1, 0) in component "03 right passive retaining saddle - PRINT"
sketch "Entry lead-in outline (2)" plane through (178.9, 0, 0) normal (1, 0, 0) x (0, 0, -1) in component "03 right passive retaining saddle - PRINT"
  line L0 (2, 44.5) -> (2, 45)
  line L1 (2, 45) -> (2.5, 45)
  line L2 (2.5, 45) -> (2, 44.5)
extrude "Entry lead-in'" cut sketch "Entry lead-in outline (2)" along normal blind 20.2 bodies 17 in component "03 right passive retaining saddle - PRINT"
ref_plane "WorkPlane1" through (0, 0, -8) normal (0, 0, 1) x (1, 0, 0) in component "06 Straight-down camera support - PRINT"
sketch "Camera support plate outline" plane through (0, 0, -8) normal (0, 0, 1) x (1, 0, 0) in component "06 Straight-down camera support - PRINT"
  line L0 (86, -23) -> (128, -23)
  line L1 (128, -23) -> (128, 17.5)
  line L2 (128, 17.5) -> (86, 17.5)
  line L3 (86, 17.5) -> (86, -23)
extrude "Camera support plate" add sketch "Camera support plate outline" along normal blind 4 separate body makes body 18 in component "06 Straight-down camera support - PRINT"
ref_plane "WorkPlane2" through (0, 0, -4) normal (0, 0, 1) x (1, 0, 0) in component "06 Straight-down camera support - PRINT"
sketch "Camera hanging spine outline" plane through (0, 0, -4) normal (0, 0, 1) x (1, 0, 0) in component "06 Straight-down camera support - PRINT"
  line L0 (86, -20.4) -> (128, -20.4)
  line L1 (128, -20.4) -> (128, -16.2)
  line L2 (128, -16.2) -> (86, -16.2)
  line L3 (86, -16.2) -> (86, -20.4)
extrude "Camera hanging spine" add sketch "Camera hanging spine outline" along normal blind 124 bodies 18 in component "06 Straight-down camera support - PRINT"
ref_plane "WorkPlane3" through (0, 0, -4) normal (0, 0, 1) x (1, 0, 0) in component "06 Straight-down camera support - PRINT"
sketch "Spine edge rib 86 outline" plane through (0, 0, -4) normal (0, 0, 1) x (1, 0, 0) in component "06 Straight-down camera support - PRINT"
  line L0 (86, -22.4) -> (90, -22.4)
  line L1 (90, -22.4) -> (90, -20.4)
  line L2 (90, -20.4) -> (86, -20.4)
  line L3 (86, -20.4) -> (86, -22.4)
extrude "Spine edge rib 86" add sketch "Spine edge rib 86 outline" along normal blind 124 bodies 18 in component "06 Straight-down camera support - PRINT"
ref_plane "WorkPlane4" through (0, 0, -4) normal (0, 0, 1) x (1, 0, 0) in component "06 Straight-down camera support - PRINT"
sketch "Spine edge rib 124 outline" plane through (0, 0, -4) normal (0, 0, 1) x (1, 0, 0) in component "06 Straight-down camera support - PRINT"
  line L0 (124, -22.4) -> (128, -22.4)
  line L1 (128, -22.4) -> (128, -20.4)
  line L2 (128, -20.4) -> (124, -20.4)
  line L3 (124, -20.4) -> (124, -22.4)
extrude "Spine edge rib 124" add sketch "Spine edge rib 124 outline" along normal blind 124 bodies 18 in component "06 Straight-down camera support - PRINT"
ref_plane "WorkPlane5" through (0, 0, -8.1) normal (0, 0, 1) x (1, 0, 0) in component "06 Straight-down camera support - PRINT"
sketch "Camera carrier M3 pilots layout" plane through (0, 0, -8.1) normal (0, 0, 1) x (1, 0, 0) in component "06 Straight-down camera support - PRINT"
  circle A0 centre (122.5, -10.65) radius 1.25
  circle A1 centre (122.5, 0.35) radius 1.25
  circle A2 centre (91.5, -10.65) radius 1.25
  circle A3 centre (91.5, 0.35) radius 1.25
extrude "Camera carrier M3 pilots" cut sketch "Camera carrier M3 pilots layout" along normal blind 4.2 bodies 18 in component "06 Straight-down camera support - PRINT"
ref_plane "WorkPlane6" through (0, 0, -8.1) normal (0, 0, 1) x (1, 0, 0) in component "06 Straight-down camera support - PRINT"
sketch "Camera nut relief layout" plane through (0, 0, -8.1) normal (0, 0, 1) x (1, 0, 0) in component "06 Straight-down camera support - PRINT"
  circle A0 centre (117.5, -7.15) radius 2.6
  circle A1 centre (117.5, 6.35) radius 2.6
  circle A2 centre (96.5, -7.15) radius 2.6
  circle A3 centre (96.5, 6.35) radius 2.6
extrude "Camera nut relief" cut sketch "Camera nut relief layout" along normal blind 2.1 bodies 18 in component "06 Straight-down camera support - PRINT"
ref_plane "WorkPlane7" through (0, 0, -8.1) normal (0, 0, 1) x (1, 0, 0) in component "06 Straight-down camera support - PRINT"
sketch "Cap screw head relief layout" plane through (0, 0, -8.1) normal (0, 0, 1) x (1, 0, 0) in component "06 Straight-down camera support - PRINT"
  circle A0 centre (122.5, -18.15) radius 2.75
  circle A1 centre (122.5, 12.85) radius 2.75
  circle A2 centre (91.5, -18.15) radius 2.75
  circle A3 centre (91.5, 12.85) radius 2.75
extrude "Cap screw head relief" cut sketch "Cap screw head relief layout" along normal blind 3.3 bodies 18 in component "06 Straight-down camera support - PRINT"
ref_plane "WorkPlane8" through (0, 0, -8.1) normal (0, 0, 1) x (1, 0, 0) in component "06 Straight-down camera support - PRINT"
sketch "Ribbon turn opening outline" plane through (0, 0, -8.1) normal (0, 0, 1) x (1, 0, 0) in component "06 Straight-down camera support - PRINT"
  line L0 (98, -24) -> (116, -24)
  line L1 (116, -24) -> (116, -16)
  line L2 (116, -16) -> (98, -16)
  line L3 (98, -16) -> (98, -24)
extrude "Ribbon turn opening" cut sketch "Ribbon turn opening outline" along normal blind 4.3 bodies 18 in component "06 Straight-down camera support - PRINT"
ref_plane "WorkPlane9" through (0, 0, -4) normal (0, 0, 1) x (1, 0, 0) in component "06 Straight-down camera support - PRINT"
sketch "Open vertical ribbon groove outline" plane through (0, 0, -4) normal (0, 0, 1) x (1, 0, 0) in component "06 Straight-down camera support - PRINT"
  line L0 (98, -20.5) -> (116, -20.5)
  line L1 (116, -20.5) -> (116, -18.8)
  line L2 (116, -18.8) -> (98, -18.8)
  line L3 (98, -18.8) -> (98, -20.5)
extrude "Open vertical ribbon groove" cut sketch "Open vertical ribbon groove outline" along normal blind 114 bodies 18 in component "06 Straight-down camera support - PRINT"
ref_plane "WorkPlane10" through (0, 0, 110) normal (0, 0, 1) x (1, 0, 0) in component "06 Straight-down camera support - PRINT"
sketch "Ribbon entry through spine outline" plane through (0, 0, 110) normal (0, 0, 1) x (1, 0, 0) in component "06 Straight-down camera support - PRINT"
  line L0 (98, -23) -> (116, -23)
  line L1 (116, -23) -> (116, -16.1)
  line L2 (116, -16.1) -> (98, -16.1)
  line L3 (98, -16.1) -> (98, -23)
extrude "Ribbon entry through spine" cut sketch "Ribbon entry through spine outline" along normal blind 3 bodies 18 in component "06 Straight-down camera support - PRINT"
ref_plane "WorkPlane11" through (0, -16.1, 0) normal (0, 1, 0) x (0, 0, 1) in component "06 Straight-down camera support - PRINT"
sketch "Panel-side M3 pilots layout" plane through (0, -16.1, 0) normal (0, 1, 0) x (1, 0, 0) in component "06 Straight-down camera support - PRINT"
  circle A0 centre (95, -84) radius 1.25
  circle A1 centre (119, -84) radius 1.25
  circle A2 centre (95, -116) radius 1.25
  circle A3 centre (119, -116) radius 1.25
extrude "Panel-side M3 pilots" cut sketch "Panel-side M3 pilots layout" against normal blind 4.4 bodies 18 in component "06 Straight-down camera support - PRINT"
ref_plane "WorkPlane1" through (0, 0, 55) normal (0, 0, 1) x (1, 0, 0) in component "REFERENCE - six mount pads - compressed"
sketch "left lower-ledge pad - 20 x 10 x 3 outline" plane through (0, 0, 55) normal (0, 0, 1) x (1, 0, 0) in component "REFERENCE - six mount pads - compressed"
  line L0 (15, 0.5) -> (35, 0.5)
  line L1 (35, 0.5) -> (35, 10.5)
  line L2 (35, 10.5) -> (15, 10.5)
  line L3 (15, 10.5) -> (15, 0.5)
extrude "left lower-ledge pad - 20 x 10 x 3" add sketch "left lower-ledge pad - 20 x 10 x 3 outline" along normal blind 2.5 separate body makes body 19 in component "REFERENCE - six mount pads - compressed"
ref_plane "WorkPlane2" through (0, 0, 67) normal (0, 0, 1) x (1, 0, 0) in component "REFERENCE - six mount pads - compressed"
sketch "left upper-ledge pad - 20 x 9 x 3 outline" plane through (0, 0, 67) normal (0, 0, 1) x (1, 0, 0) in component "REFERENCE - six mount pads - compressed"
  line L0 (15, 13) -> (35, 13)
  line L1 (35, 13) -> (35, 22)
  line L2 (35, 22) -> (15, 22)
  line L3 (15, 22) -> (15, 13)
extrude "left upper-ledge pad - 20 x 9 x 3" add sketch "left upper-ledge pad - 20 x 9 x 3 outline" along normal blind 2.5 separate body makes body 20 in component "REFERENCE - six mount pads - compressed"
ref_plane "WorkPlane3" through (0, 0, -2.5) normal (0, 0, 1) x (1, 0, 0) in component "REFERENCE - six mount pads - compressed"
sketch "left underside retaining pad - 16 x 14 x 3 outline" plane through (0, 0, -2.5) normal (0, 0, 1) x (1, 0, 0) in component "REFERENCE - six mount pads - compressed"
  line L0 (17, 30) -> (33, 30)
  line L1 (33, 30) -> (33, 44)
  line L2 (33, 44) -> (17, 44)
  line L3 (17, 44) -> (17, 30)
extrude "left underside retaining pad - 16 x 14 x 3" add sketch "left underside retaining pad - 16 x 14 x 3 outline" along normal blind 2.5 separate body makes body 21 in component "REFERENCE - six mount pads - compressed"